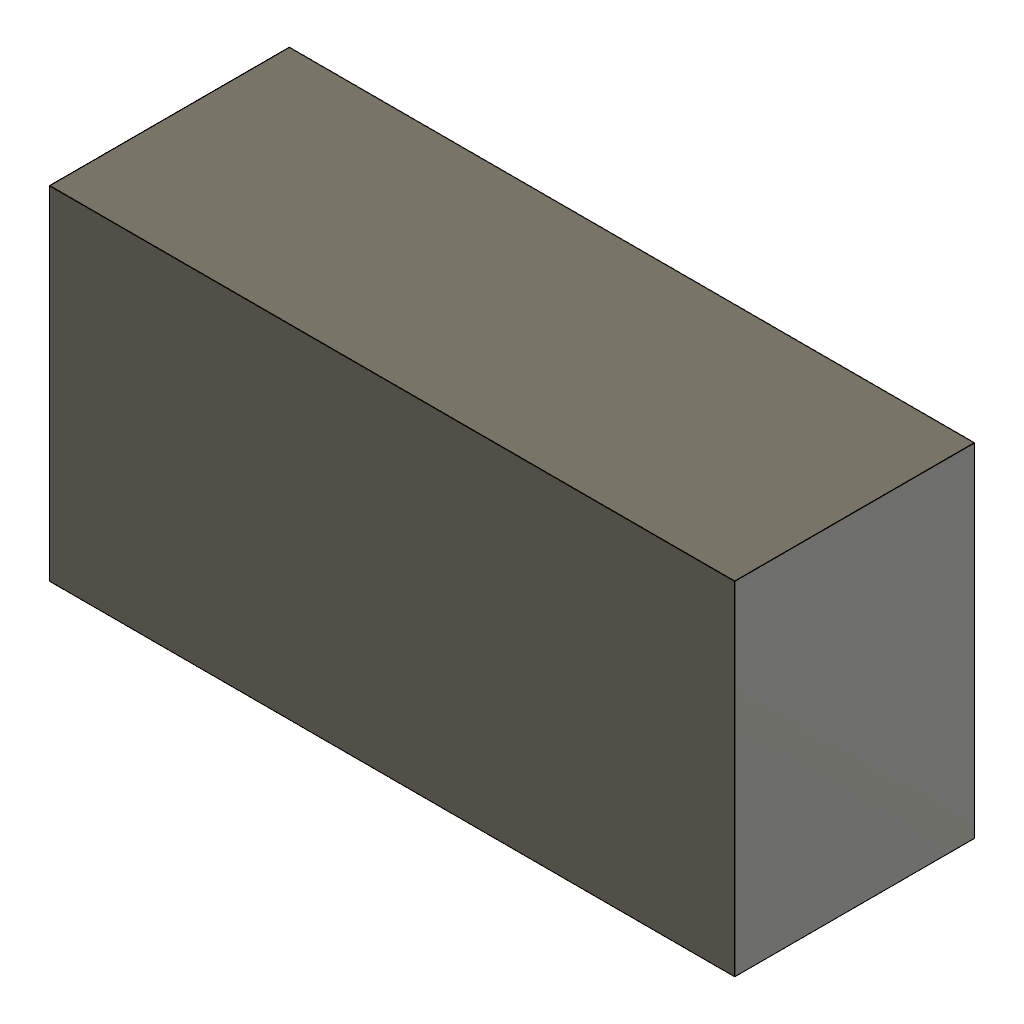
params_renamed_suppressed (Autodesk Fusion 360 design; units mm, degrees)
part number: 2026-11-10-15-06-56-882
Autodesk Fusion 360 part; units mm, degrees
sketch "base_outline" plane through (0, 0, 0) normal (0, 0, 1) x (1, 0, 0)
  line L0 (0, 0) -> (20, 0)
  line L1 (20, 0) -> (20, 10)
  line L2 (20, 10) -> (0, 10)
  line L3 (0, 10) -> (0, 0)
  dimension "d3" = 20
  measures "d3" horizontal distance of L0.start L0.end
extrude "main_block" add sketch "base_outline" along normal blind 7
sketch "hole_sketch" plane through (0, 0, 0) normal (0, 0, 1) x (1, 0, 0)
  circle A0 centre (10, 5) radius 2
extrude "suppressed_hole" [suppressed]
equation "width = 20 mm" comment "block width"
equation "depth = 7 mm" comment "extrude depth"
equation "d3 = width"
equation "d4 = depth"
